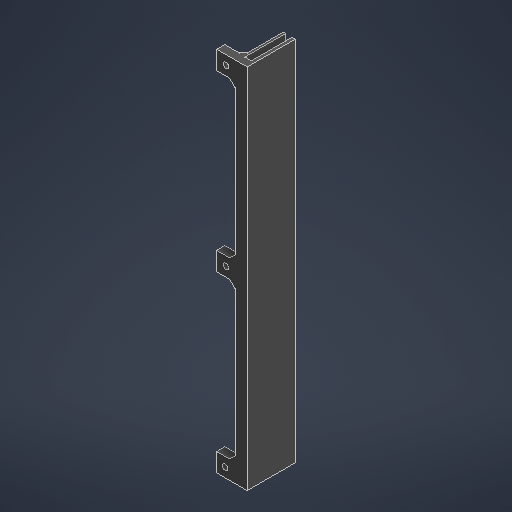
# Autodesk Inventor part: Front_Rail_Wall
Saved by Autodesk Inventor 2027.1 (Build 311270010, 270A)
## iProperties
Created: 2026-10-10
Part Number: Front_Rail_Wall
Material: 一般
Document SubType Name: Modeling
Designer: Takuya Kamada
Density: 1 g/cm^3
Appearance: 一般
Author: Takuya Kamada
Autodesk Inventor part; units mm, degrees
ref_plane "YZ Plane" through (0, 0, 0) normal (1, 0, 0) x (0, 1, 0)
sketch "スケッチ1" plane through (0, 0, 0) normal (0, 0, 1) x (1, 0, 0)
  line L0 (-1.2428, 0.7068) -> (5.2572, 0.7068) projected
  line L1 (0, -198) -> (3, -198) projected
  line L2 (3, 0) -> (3, -198) projected
  line L3 (0, 0) -> (3, 0) projected
  line L4 (0, 0) -> (0, -198) projected
  arc A0 (-1.2428, 0.7068) -> (-84.9598, 202.8177) centre (-287.0708, 0.7068) ccw projected
  arc A1 (5.2572, 0.7068) -> (-80.3637, 207.4139) centre (-287.0708, 0.7068) ccw projected
  circle A2 centre (-287.0708, 0.7068) radius 285.828 construction
  circle A3 centre (-287.0708, 0.7068) radius 292.328 construction
  line L5 (-1.2436, 0) -> (5.2564, 0)
  line L6 (-1.2436, 0) -> (5.2564, 0)
  line L7 (5.2564, 0) -> (5.2564, -198)
  line L8 (5.2564, -198) -> (-1.2436, -198)
  line L9 (-1.2436, -198) -> (-1.2436, 0)
  line L10 (-0.2428, 0.7068) -> (3.2572, 0.7068) projected
  arc A4 (-0.2428, 0.7068) -> (-84.2527, 203.5248) centre (-287.0708, 0.7068) ccw projected
  line L11 (-81.7779, 205.9997) -> (-84.2527, 203.5248) projected
  arc A5 (3.2572, 0.7068) -> (-81.7779, 205.9997) centre (-287.0708, 0.7068) ccw projected
  line L12 (-0.2428, 0.7068) -> (3.2572, 0.7068) projected
  arc A6 (-0.2428, 0.7068) -> (-84.2527, 203.5248) centre (-287.0708, 0.7068) ccw projected
  line L13 (-81.7779, 205.9997) -> (-84.2527, 203.5248) projected
  arc A7 (3.2572, 0.7068) -> (-81.7779, 205.9997) centre (-287.0708, 0.7068) ccw projected
  line L14 (0, 0) -> (3.5, 0)
  line L15 (3.5, 0) -> (3.5, -198)
  line L16 (3.5, -198) -> (0, -198)
  line L17 (0, -198) -> (0, 0)
  dimension "d0" = 3.5
  constraints: 18 end point, 4 parallel, 3 point on line, 2 coincident, 2 horizontal, 2 horizontal alignment, 2 perpendicular, 2 point on circle, 1 centre point, 6 other
  measures "d0" distance between parallel lines of L15 L17
ref_plane "作業平面1" through (-144.1568, -2.5432, 26) normal (0, 0, 1) x (0.7071, 0.7071, 0)
extrude "押し出し1" add sketch "スケッチ1" along normal up to surface (26 mm away) contours L8 L9 L5 L4 | L15 L5 L7 L8
sketch "スケッチ2" plane through (-1.2436, -198, 26) normal (0, 0, 1) x (1, 0, 0)
  line L0 (0, 0) -> (0, 198) projected
  line L1 (1.2436, 0) -> (0, 0) projected
  line L2 (1.2436, 198) -> (1.2436, 0) projected
  line L3 (0, 198) -> (1.2436, 198) projected
  line L4 (6.5, 198) -> (6.5, 0) projected
  line L5 (4.7436, 198) -> (6.5, 198) projected
  line L6 (4.7436, 0) -> (4.7436, 198) projected
  line L7 (6.5, 0) -> (4.7436, 0) projected
  line L8 (0, 198) -> (6.5, 198)
  line L9 (6.5, 198) -> (6.5, 0)
  line L10 (6.5, 0) -> (0, 0)
  line L11 (0, 0) -> (0, 198)
  point P0 (1.2436, 198)
  constraints: 8 end point, 2 parallel, 1 horizontal, 1 perpendicular
ref_plane "作業平面2" through (-143.6568, -1.0432, 22) normal (0, 0, -1) x (-0.7071, 0.7071, 0)
extrude "押し出し2" add sketch "スケッチ2" against normal up to surface (4 mm away) contours L2 L8 L6 L10
sketch "スケッチ4" plane through (-1.2436, -198, 0) normal (-1, 0, 0) x (0, 0, 1)
  line L0 (0, 198) -> (26, 198) projected
  line L1 (26, 198) -> (21.6, 198)
  line L2 (21.6, 198) -> (21.6, 188)
  line L3 (21.6, 188) -> (26, 188)
  line L4 (26, 188) -> (26, 198)
  line L5 (0, 0) -> (26, 0) projected
  line L6 (26, 0) -> (21.6, 0)
  line L7 (21.6, 0) -> (21.6, 10)
  line L8 (21.6, 10) -> (26, 10)
  line L9 (26, 10) -> (26, 0)
  line L10 (26, 104) -> (21.6, 104)
  line L11 (21.6, 104) -> (21.6, 94)
  line L12 (21.6, 94) -> (26, 94)
  line L13 (26, 94) -> (26, 104)
  line L14 (26, 0) -> (26, 198) projected
  point P0 (26, 99)
  point P1 (26, 99)
  point P2 (26, 99)
  point P3 (21.6, 0)
  dimension "d5" = 4.4
  dimension "d6" = 10
  dimension "d9" = 4.4
  dimension "d10" = 10
  dimension "d11" = 4.4
  dimension "d12" = 10
  constraints: 24 end point, 6 parallel, 4 midpoint, 3 horizontal, 3 perpendicular, 1 coincident
  measures "d5" distance between parallel lines of L4 L2
  measures "d6" distance of L1.end L2.end
  measures "d9" distance of L7.end L8.end
  measures "d10" distance of L6.end L7.end
  measures "d11" distance of L12.end L11.end
  measures "d12" distance of L11.end L10.end
extrude "押し出し3" add sketch "スケッチ4" along normal blind 10
chamfer "面取り1" distance 3 angle 45 4 edges at (-1.2436, -94, 23.8) (-1.2436, -104, 23.8) (-1.2436, -10, 23.8) (-1.2436, -188, 23.8)
sketch "スケッチ5" plane through (5.2564, -198, 26) normal (0, 0, 1) x (1, 0, 0)
  line L0 (0, 0) -> (-16.5, 0) projected
  line L1 (0, 198) -> (0, 0) projected
  line L2 (0, 198) -> (-16.5, 198) projected
  line L3 (-16.5, 188) -> (-16.5, 198) projected
  line L4 (-9.5, 188) -> (-16.5, 188) projected
  line L5 (-6.5, 185) -> (-9.5, 188) projected
  line L6 (-6.5, 107) -> (-6.5, 185) projected
  line L7 (-9.5, 104) -> (-6.5, 107) projected
  line L8 (-9.5, 104) -> (-16.5, 104) projected
  line L9 (-16.5, 94) -> (-16.5, 104) projected
  line L10 (-9.5, 94) -> (-16.5, 94) projected
  line L11 (-6.5, 91) -> (-9.5, 94) projected
  line L12 (-6.5, 13) -> (-6.5, 91) projected
  line L13 (-9.5, 10) -> (-6.5, 13) projected
  line L14 (-9.5, 10) -> (-16.5, 10) projected
  line L15 (-16.5, 0) -> (-16.5, 10) projected
  line L16 (-16.5, 188) -> (-6.5, 188)
  line L17 (-6.5, 188) -> (-6.5, 198)
  line L18 (-6.5, 198) -> (-16.5, 198)
  line L19 (-16.5, 198) -> (-16.5, 188)
  line L20 (-16.5, 104) -> (-6.5, 104)
  line L21 (-6.5, 104) -> (-6.5, 94)
  line L22 (-6.5, 94) -> (-16.5, 94)
  line L23 (-16.5, 94) -> (-16.5, 104)
  line L24 (0, 0) -> (-16.5, 0) projected
  line L25 (-16.5, 0) -> (-6.5, 0)
  line L26 (-6.5, 0) -> (-6.5, 10)
  line L27 (-6.5, 10) -> (-16.5, 10)
  line L28 (-16.5, 10) -> (-16.5, 0)
  line L29 (-8.65, 3.1236) -> (-11.9, 1.2472)
  line L30 (-11.9, 1.2472) -> (-15.15, 3.1236)
  line L31 (-15.15, 3.1236) -> (-15.15, 6.8764)
  line L32 (-15.15, 6.8764) -> (-11.9, 8.7528)
  line L33 (-11.9, 8.7528) -> (-8.65, 6.8764)
  line L34 (-8.65, 6.8764) -> (-8.65, 3.1236)
  line L35 (-8.65, 97.3546) -> (-11.5, 95.7091)
  line L36 (-11.5, 95.7091) -> (-14.35, 97.3546)
  line L37 (-14.35, 97.3546) -> (-14.35, 100.6454)
  line L38 (-14.35, 100.6454) -> (-11.5, 102.2909)
  line L39 (-11.5, 102.2909) -> (-8.65, 100.6454)
  line L40 (-8.65, 100.6454) -> (-8.65, 97.3546)
  line L41 (-8.65, 191.3546) -> (-11.5, 189.7091)
  line L42 (-11.5, 189.7091) -> (-14.35, 191.3546)
  line L43 (-14.35, 191.3546) -> (-14.35, 194.6454)
  line L44 (-14.35, 194.6454) -> (-11.5, 196.2909)
  line L45 (-11.5, 196.2909) -> (-8.65, 194.6454)
  line L46 (-8.65, 194.6454) -> (-8.65, 191.3546)
  point P0 (-5.2564, 198)
  point P1 (-11.9, 5)
  point P2 (-11.5, 99)
  point P3 (-11.5, 193)
  point P4 (-8.65, 193)
  point P5 (-14.35, 99)
  point P6 (-8.65, 99)
  point P7 (-15.15, 5)
  point P8 (-8.65, 5)
  dimension "d18" = 5.7
  dimension "d19" = 5.7
  dimension "d20" = 6.5
  constraints: 60 end point, 6 parallel, 5 midpoint, 4 point on line, 3 horizontal, 3 perpendicular, 39 other
  measures "d18" distance between parallel lines of L43 L46
  measures "d19" distance of point (-14.35, 99) point (-8.65, 99)
  measures "d20" distance of point (-15.15, 5) point (-8.65, 5)
extrude "押し出し4" cut sketch "スケッチ5" against normal up to surface (4.4 mm away) contours L29 L30 L31 L32 L33 L34 | L35 L36 L37 L38 L39 L40 | L41 L42 L43 L44 L45 L46
sketch "スケッチ7" plane through (5.2564, -198, 26) normal (0, 0, 1) x (1, 0, 0)
  line L0 (-8.65, 191.3546) -> (-11.5, 189.7091) projected
  line L1 (-11.5, 189.7091) -> (-14.35, 191.3546) projected
  line L2 (-14.35, 191.3546) -> (-14.35, 194.6454) projected
  line L3 (-14.35, 194.6454) -> (-11.5, 196.2909) projected
  line L4 (-11.5, 196.2909) -> (-8.65, 194.6454) projected
  line L5 (-8.65, 194.6454) -> (-8.65, 191.3546) projected
  line L6 (-8.65, 3.1236) -> (-11.9, 1.2472) projected
  line L7 (-11.9, 1.2472) -> (-15.15, 3.1236) projected
  line L8 (-15.15, 3.1236) -> (-15.15, 6.8764) projected
  line L9 (-15.15, 6.8764) -> (-11.9, 8.7528) projected
  line L10 (-11.9, 8.7528) -> (-8.65, 6.8764) projected
  line L11 (-8.65, 6.8764) -> (-8.65, 3.1236) projected
  line L12 (-11.5, 95.7091) -> (-14.35, 97.3546) projected
  line L13 (-14.35, 97.3546) -> (-14.35, 100.6454) projected
  line L14 (-14.35, 100.6454) -> (-11.5, 102.2909) projected
  line L15 (-11.5, 102.2909) -> (-8.65, 100.6454) projected
  line L16 (-8.65, 100.6454) -> (-8.65, 97.3546) projected
  line L17 (-8.65, 97.3546) -> (-11.5, 95.7091) projected
  line L18 (0, 0) -> (-16.5, 0) projected
  line L19 (0, 198) -> (0, 0) projected
  line L20 (0, 198) -> (-16.5, 198) projected
  line L21 (-16.5, 188) -> (-16.5, 198) projected
  line L22 (-9.5, 188) -> (-16.5, 188) projected
  line L23 (-6.5, 185) -> (-9.5, 188) projected
  line L24 (-6.5, 107) -> (-6.5, 185) projected
  line L25 (-9.5, 104) -> (-6.5, 107) projected
  line L26 (-9.5, 104) -> (-16.5, 104) projected
  line L27 (-16.5, 94) -> (-16.5, 104) projected
  line L28 (-9.5, 94) -> (-16.5, 94) projected
  line L29 (-6.5, 91) -> (-9.5, 94) projected
  line L30 (-6.5, 13) -> (-6.5, 91) projected
  line L31 (-9.5, 10) -> (-6.5, 13) projected
  line L32 (-9.5, 10) -> (-16.5, 10) projected
  line L33 (-16.5, 0) -> (-16.5, 10) projected
  circle A0 centre (-11.5, 193) radius 1.5
  circle A1 centre (-11.5, 99) radius 1.5
  circle A2 centre (-11.9386, 4.9332) radius 1.5
  point P0 (-5.2564, 198)
  dimension "d23" = 3
  dimension "d24" = 3
  dimension "d25" = 3
  constraints: 3 centre point
  measures "d23" diameter of A0
  measures "d24" diameter of A1
  measures "d25" diameter of A2
extrude "押し出し5" add sketch "スケッチ7" against normal blind 2 contours L0 L1 L2 L3 L4 L5 | L6 L7 L8 L9 L10 L11 | L12 L13 L14 L15 L16 L17
chamfer "面取り2" distance 2.15 angle 45 3 edges at (-1.2436, -191.5, 21.6) (-1.2436, -99, 21.6) (-1.2436, -6.5, 21.6)
equation "\"d9\" = d5"
equation "\"d10\" = d6"
equation "\"d19\" = d18"
